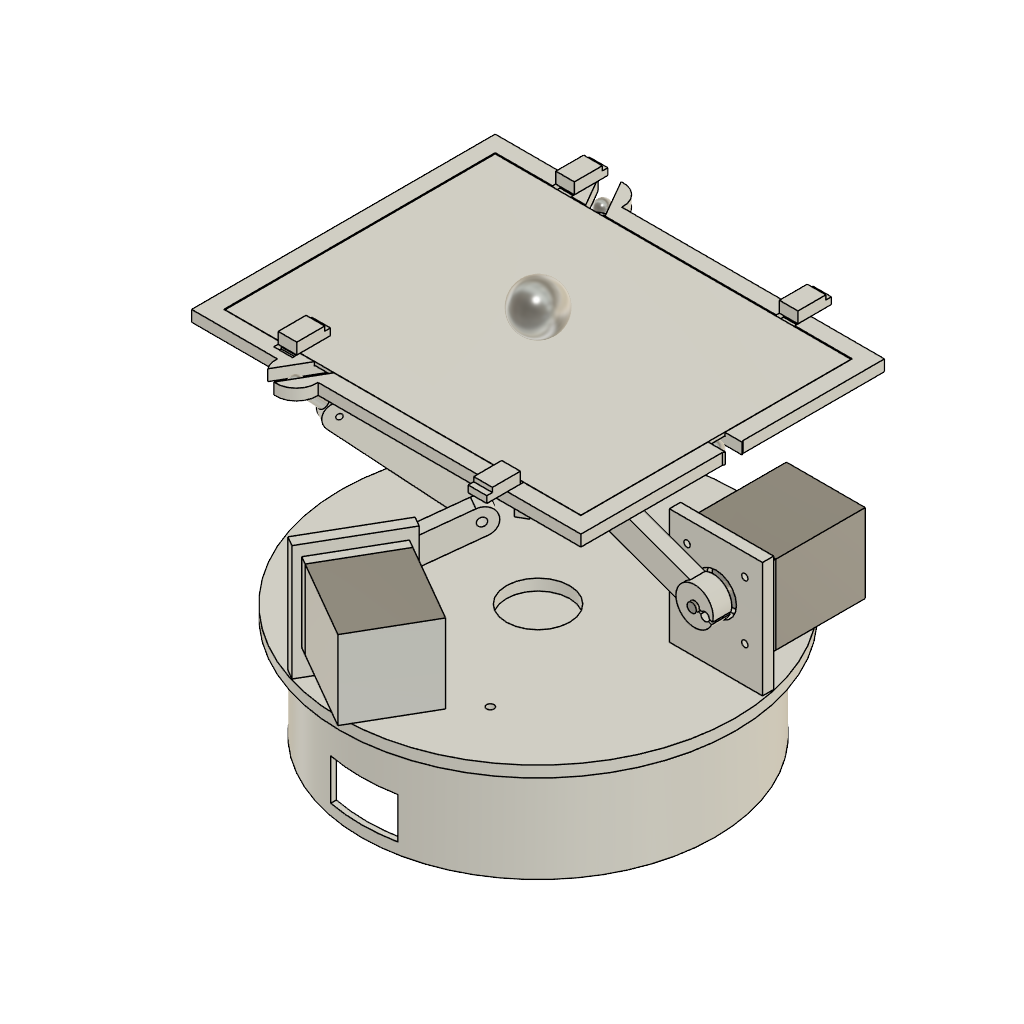
BallBalancer (Autodesk Fusion 360 design; units mm, degrees)
part number: 2026-11-05-17-29-33-825
part number: 2026-11-05-17-29-34-992
part number: 2026-11-05-17-29-35-798
part number: 2026-11-05-17-29-36-320
part number: 2026-11-05-17-29-37-063
description: 22 mm M3 tie rod with ball ends, bought in
part number: 2026-11-05-17-29-37-542
description: Reference geometry, not a printed part
part number: 2026-11-05-17-29-37-865
part number: 2026-11-05-17-29-38-263
part number: 2026-11-05-17-29-38-994
description: 8.4 inch 4 wire resistive panel, reference geometry
part number: 2026-11-05-17-29-40-592
description: 1 inch steel bearing ball, reference geometry
part number: 2026-11-05-17-29-40-774
part number: 2026-11-05-17-29-40-973
Autodesk Fusion 360 part; units mm, degrees
note: some values were not read from the file. Set by a fixed rule: which sketch regions a step uses.
sketch "plate_outline" plane through (0, 0, 0) normal (0, 0, 1) x (1, 0, 0) in component "base_plate"
  circle A0 centre (0, 0) radius 106
extrude "Extrude1" add sketch "plate_outline" against normal blind 6 makes body 1 in component "base_plate"
sketch "flange_0_footprint" plane through (0, 0, 0) normal (0, 0, 1) x (1, 0, 0) in component "base_plate"
  line L0 (53, 23.5) -> (103, 23.5)
  line L1 (103, 23.5) -> (103, 17.5)
  line L2 (103, 17.5) -> (53, 17.5)
  line L3 (53, 17.5) -> (53, 23.5)
extrude "Extrude2" add sketch "flange_0_footprint" along normal blind 62 bodies 1 in component "base_plate"
sketch "flange_1_footprint" plane through (0, 0, 0) normal (0, 0, 1) x (1, 0, 0) in component "base_plate"
  line L0 (-46.8516, 34.1493) -> (-71.8516, 77.4506)
  line L1 (-71.8516, 77.4506) -> (-66.6554, 80.4506)
  line L2 (-66.6554, 80.4506) -> (-41.6554, 37.1493)
  line L3 (-41.6554, 37.1493) -> (-46.8516, 34.1493)
extrude "Extrude3" add sketch "flange_1_footprint" along normal blind 62 bodies 1 in component "base_plate"
sketch "flange_2_footprint" plane through (0, 0, 0) normal (0, 0, 1) x (1, 0, 0) in component "base_plate"
  line L0 (-6.1484, -57.6493) -> (-31.1484, -100.9506)
  line L1 (-31.1484, -100.9506) -> (-36.3446, -97.9506)
  line L2 (-36.3446, -97.9506) -> (-11.3446, -54.6493)
  line L3 (-11.3446, -54.6493) -> (-6.1484, -57.6493)
extrude "Extrude4" add sketch "flange_2_footprint" along normal blind 62 bodies 1 in component "base_plate"
sketch "leg_0_plane_axis" plane through (0, 0, 0) normal (0, 0, 1) x (1, 0, 0) in component "base_plate"
  line L0 (0, 0) -> (150, 0)
ref_plane "WorkPlane1" through (75, 0, 0) normal (0, -1, 0) x (1, 0, 0) in component "base_plate"
sketch "flange_0_holes" plane through (0, 0, 0) normal (0, -1, 0) x (-1, 0, 0) in component "base_plate"
  circle A0 centre (-62.5, -19.5) radius 1.7
  circle A1 centre (-62.5, -50.5) radius 1.7
  circle A2 centre (-93.5, -19.5) radius 1.7
  circle A3 centre (-93.5, -50.5) radius 1.7
  circle A4 centre (-78, -35) radius 11
extrude "Extrude5" cut sketch "flange_0_holes" along normal mid plane 160 bodies 1 in component "base_plate"
sketch "leg_1_plane_axis" plane through (0, 0, 0) normal (0, 0, 1) x (1, 0, 0) in component "base_plate"
  line L0 (0, 0) -> (-75, 129.9038)
ref_plane "WorkPlane2" through (-37.5, 64.9519, 0) normal (0.866025, 0.5, 0) x (-0.5, 0.866025, 0) in component "base_plate"
sketch "flange_1_holes" plane through (0, 0, 0) normal (0.866025, 0.5, 0) x (-0.5, 0.866025, 0) in component "base_plate"
  circle A0 centre (62.5, 19.5) radius 1.7
  circle A1 centre (62.5, 50.5) radius 1.7
  circle A2 centre (93.5, 19.5) radius 1.7
  circle A3 centre (93.5, 50.5) radius 1.7
  circle A4 centre (78, 35) radius 11
extrude "Extrude6" cut sketch "flange_1_holes" along normal mid plane 160 bodies 1 in component "base_plate"
sketch "leg_2_plane_axis" plane through (0, 0, 0) normal (0, 0, 1) x (1, 0, 0) in component "base_plate"
  line L0 (0, 0) -> (-75, -129.9038)
ref_plane "WorkPlane3" through (-37.5, -64.9519, 0) normal (-0.866025, 0.5, 0) x (-0.5, -0.866025, 0) in component "base_plate"
sketch "flange_2_holes" plane through (0, 0, 0) normal (-0.866025, 0.5, 0) x (-0.5, -0.866025, 0) in component "base_plate"
  circle A0 centre (62.5, 19.5) radius 1.7
  circle A1 centre (62.5, 50.5) radius 1.7
  circle A2 centre (93.5, 19.5) radius 1.7
  circle A3 centre (93.5, 50.5) radius 1.7
  circle A4 centre (78, 35) radius 11
extrude "Extrude7" cut sketch "flange_2_holes" along normal mid plane 160 bodies 1 in component "base_plate"
sketch "insert_holes" plane through (0, 0, 0) normal (0, 0, 1) x (1, 0, 0) in component "base_plate"
  circle A0 centre (35, 60.6218) radius 2
  circle A1 centre (-70, 0) radius 2
  circle A2 centre (35, -60.6218) radius 2
extrude "Extrude8" cut sketch "insert_holes" against normal blind 6 bodies 1 in component "base_plate"
sketch "cable_hole" plane through (0, 0, 0) normal (0, 0, 1) x (1, 0, 0) in component "base_plate"
  circle A0 centre (0, 0) radius 17
extrude "Extrude9" cut sketch "cable_hole" along normal mid plane 160 bodies 1 in component "base_plate"
sketch "stand_outline" plane through (0, 0, 0) normal (0, 0, 1) x (1, 0, 0) in component "base_stand"
  circle A0 centre (0, 0) radius 95
extrude "Extrude1'" add sketch "stand_outline" against normal blind 55 from surface at -6 separate body makes body 2 in component "base_stand"
sketch "stand_cavity" plane through (0, 0, 0) normal (0, 0, 1) x (1, 0, 0) in component "base_stand"
  circle A0 centre (0, 0) radius 92
extrude "Extrude2'" cut sketch "stand_cavity" against normal blind 51 from surface at -10 bodies 2 in component "base_stand"
sketch "stand_bolt_holes" plane through (0, 0, 0) normal (0, 0, 1) x (1, 0, 0) in component "base_stand"
  circle A0 centre (35, 60.6218) radius 1.7
  circle A1 centre (-70, 0) radius 1.7
  circle A2 centre (35, -60.6218) radius 1.7
extrude "Extrude3'" cut sketch "stand_bolt_holes" along normal mid plane 160 bodies 2 in component "base_stand"
sketch "protoboard_inserts" plane through (0, 0, 0) normal (0, 0, 1) x (1, 0, 0) in component "base_stand"
  circle A0 centre (-30, -30) radius 2
  circle A1 centre (30, -30) radius 2
  circle A2 centre (30, 30) radius 2
  circle A3 centre (-30, 30) radius 2
extrude "Extrude4'" cut sketch "protoboard_inserts" against normal blind 6 from surface at -4 bodies 2 in component "base_stand"
sketch "cable_slot" plane through (0, 0, 0) normal (0, 0, 1) x (1, 0, 0) in component "base_stand"
  line L0 (-18, -100) -> (18, -100)
  line L1 (18, -100) -> (18, -87)
  line L2 (18, -87) -> (-18, -87)
  line L3 (-18, -87) -> (-18, -100)
extrude "Extrude5'" cut sketch "cable_slot" along normal blind 22 from surface at -55 bodies 2 in component "base_stand"
sketch "crank_profile" plane through (0, 0, 0) normal (0, 0, 1) x (1, 0, 0) in component "link_1_crank"
  circle A0 centre (0, 0) radius 10
  circle A1 centre (-55, 0) radius 7
  line L0 (0, -7) -> (-55, -7)
  line L1 (0, 7) -> (-55, 7)
  line L2 (0, -7) -> (0, 7)
  line L3 (-55, -7) -> (-55, 7)
extrude "Extrude1''" add sketch "crank_profile" along normal blind 8 separate body makes body 3 in component "link_1_crank"
sketch "hub" plane through (0, 0, 0) normal (0, 0, 1) x (1, 0, 0) in component "link_1_crank"
  circle A0 centre (0, 0) radius 10
extrude "Extrude2''" add sketch "hub" along normal blind 10 bodies 3 in component "link_1_crank"
sketch "shaft_bore" plane through (0, 0, 0) normal (0, 0, 1) x (1, 0, 0) in component "link_1_crank"
  circle A0 centre (0, 0) radius 2.575
extrude "Extrude3''" cut sketch "shaft_bore" along normal mid plane 160 bodies 3 in component "link_1_crank"
sketch "clamp_slot" plane through (0, 0, 0) normal (0, 0, 1) x (1, 0, 0) in component "link_1_crank"
  line L0 (1, -0.7) -> (11, -0.7)
  line L1 (11, -0.7) -> (11, 0.7)
  line L2 (11, 0.7) -> (1, 0.7)
  line L3 (1, 0.7) -> (1, -0.7)
extrude "Extrude4''" cut sketch "clamp_slot" along normal mid plane 160 bodies 3 in component "link_1_crank"
sketch "clamp_screw" plane through (0, 0, 0) normal (0, 0, 1) x (1, 0, 0) in component "link_1_crank"
  circle A0 centre (6, 0) radius 2.25
extrude "Extrude5''" cut sketch "clamp_screw" along normal blind 12 from surface at -1 bodies 3 in component "link_1_crank"
sketch "knee_bore" plane through (0, 0, 0) normal (0, 0, 1) x (1, 0, 0) in component "link_1_crank"
  circle A0 centre (-55, 0) radius 2.25
extrude "Extrude6'" cut sketch "knee_bore" along normal mid plane 160 bodies 3 in component "link_1_crank"
sketch "coupler_profile" plane through (0, 0, 0) normal (0, 0, 1) x (1, 0, 0) in component "link_2_coupler"
  circle A0 centre (0, 0) radius 7
  circle A1 centre (73, 0) radius 7
  line L0 (0, -7) -> (73, -7)
  line L1 (0, 7) -> (73, 7)
  line L2 (0, -7) -> (0, 7)
  line L3 (73, -7) -> (73, 7)
extrude "Extrude1'''" add sketch "coupler_profile" along normal blind 8 separate body makes body 4 in component "link_2_coupler"
sketch "coupler_bores" plane through (0, 0, 0) normal (0, 0, 1) x (1, 0, 0) in component "link_2_coupler"
  circle A0 centre (0, 0) radius 2.25
  circle A1 centre (73, 0) radius 1.45
extrude "Extrude2'''" cut sketch "coupler_bores" along normal mid plane 160 bodies 4 in component "link_2_coupler"
sketch "rod_axis" plane through (0, 0, 0) normal (0, 0, 1) x (1, 0, 0) in component "tie_rod"
  line L0 (0, 0) -> (22, 0)
  line L1 (7, 0) -> (7, 3)
  line L2 (7, 3) -> (22, 3)
  line L3 (22, 3) -> (22, 0)
revolve "Revolve1" add sketch "rod_axis" angle 360 about axis through (0, 0, 0) along (1, 0, 0) separate body makes body 5 in component "tie_rod"
sketch "ball_end" plane through (0, 0, 0) normal (0, 0, 1) x (1, 0, 0) in component "tie_rod"
  line L0 (18, 0) -> (26, 0)
  arc A0 (26, 0) -> (18, 0) centre (22, 0) ccw
revolve "Revolve2" add sketch "ball_end" angle 360 about axis through (18, 0, 0) along (1, 0, 0) bodies 5 in component "tie_rod"
sketch "motor_body" plane through (0, 0, 0) normal (0, 0, 1) x (1, 0, 0) in component "nema17_reference"
  line L0 (-21.15, -21.15) -> (21.15, -21.15)
  line L1 (21.15, -21.15) -> (21.15, 21.15)
  line L2 (21.15, 21.15) -> (-21.15, 21.15)
  line L3 (-21.15, 21.15) -> (-21.15, -21.15)
extrude "Extrude1''''" add sketch "motor_body" against normal blind 48 separate body makes body 6 in component "nema17_reference"
sketch "pilot_boss" plane through (0, 0, 0) normal (0, 0, 1) x (1, 0, 0) in component "nema17_reference"
  circle A0 centre (0, 0) radius 11
extrude "Extrude2''''" add sketch "pilot_boss" along normal blind 2 bodies 6 in component "nema17_reference"
sketch "shaft" plane through (0, 0, 0) normal (0, 0, 1) x (1, 0, 0) in component "nema17_reference"
  circle A0 centre (0, 0) radius 2.5
extrude "Extrude3'''" add sketch "shaft" along normal blind 24 bodies 6 in component "nema17_reference"
sketch "spacer_outline" plane through (0, 0, 0) normal (0, 0, 1) x (1, 0, 0) in component "motor_spacer"
  line L0 (-21.15, -21.15) -> (21.15, -21.15)
  line L1 (21.15, -21.15) -> (21.15, 21.15)
  line L2 (21.15, 21.15) -> (-21.15, 21.15)
  line L3 (-21.15, 21.15) -> (-21.15, -21.15)
extrude "Extrude1'''''" add sketch "spacer_outline" along normal blind 5 separate body makes body 7 in component "motor_spacer"
sketch "spacer_holes" plane through (0, 0, 0) normal (0, 0, 1) x (1, 0, 0) in component "motor_spacer"
  circle A0 centre (-15.5, -15.5) radius 1.7
  circle A1 centre (-15.5, 15.5) radius 1.7
  circle A2 centre (15.5, -15.5) radius 1.7
  circle A3 centre (15.5, 15.5) radius 1.7
  circle A4 centre (0, 0) radius 11.5
extrude "Extrude2'''''" cut sketch "spacer_holes" along normal mid plane 160 bodies 7 in component "motor_spacer"
sketch "frame_outline" plane through (0, 0, 0) normal (0, 0, 1) x (1, 0, 0) in component "platform_frame"
  line L0 (-104.5, -81.5) -> (104.5, -81.5)
  line L1 (104.5, -81.5) -> (104.5, 81.5)
  line L2 (104.5, 81.5) -> (-104.5, 81.5)
  line L3 (-104.5, 81.5) -> (-104.5, -81.5)
  circle A0 centre (95, 0) radius 11
  circle A1 centre (-47.5, 82.2724) radius 11
  circle A2 centre (-47.5, -82.2724) radius 11
extrude "Extrude1''''''" add sketch "frame_outline" along normal blind 6 separate body makes body 8 in component "platform_frame"
sketch "panel_recess" plane through (0, 0, 0) normal (0, 0, 1) x (1, 0, 0) in component "platform_frame"
  line L0 (-95.8, -72.8) -> (95.8, -72.8)
  line L1 (95.8, -72.8) -> (95.8, 72.8)
  line L2 (95.8, 72.8) -> (-95.8, 72.8)
  line L3 (-95.8, 72.8) -> (-95.8, -72.8)
extrude "Extrude2''''''" cut sketch "panel_recess" against normal blind 2 from surface at 6 bodies 8 in component "platform_frame"
sketch "frame_window" plane through (0, 0, 0) normal (0, 0, 1) x (1, 0, 0) in component "platform_frame"
  line L0 (-83.5, -60.5) -> (83.5, -60.5)
  line L1 (83.5, -60.5) -> (83.5, 60.5)
  line L2 (83.5, 60.5) -> (-83.5, 60.5)
  line L3 (-83.5, 60.5) -> (-83.5, -60.5)
extrude "Extrude3''''" cut sketch "frame_window" along normal mid plane 160 bodies 8 in component "platform_frame"
sketch "ear_clevis_slots" plane through (0, 0, 0) normal (0, 0, 1) x (1, 0, 0) in component "platform_frame"
  line L0 (82, 4.5) -> (108, 4.5)
  line L1 (108, 4.5) -> (108, -4.5)
  line L2 (108, -4.5) -> (82, -4.5)
  line L3 (82, -4.5) -> (82, 4.5)
  line L4 (-44.8971, 68.7641) -> (-57.8971, 91.2807)
  line L5 (-57.8971, 91.2807) -> (-50.1029, 95.7807)
  line L6 (-50.1029, 95.7807) -> (-37.1029, 73.2641)
  line L7 (-37.1029, 73.2641) -> (-44.8971, 68.7641)
  line L8 (-37.1029, -73.2641) -> (-50.1029, -95.7807)
  line L9 (-50.1029, -95.7807) -> (-57.8971, -91.2807)
  line L10 (-57.8971, -91.2807) -> (-44.8971, -68.7641)
  line L11 (-44.8971, -68.7641) -> (-37.1029, -73.2641)
extrude "Extrude4'''" cut sketch "ear_clevis_slots" along normal mid plane 160 bodies 8 in component "platform_frame"
sketch "ear_bores" plane through (0, 0, 0) normal (0, 0, 1) x (1, 0, 0) in component "platform_frame"
  circle A0 centre (95, 0) radius 1.7
  circle A1 centre (-47.5, 82.2724) radius 1.7
  circle A2 centre (-47.5, -82.2724) radius 1.7
extrude "Extrude5'''" cut sketch "ear_bores" along normal mid plane 160 bodies 8 in component "platform_frame"
sketch "clip_slots" plane through (0, 0, 0) normal (0, 0, 1) x (1, 0, 0) in component "platform_frame"
  line L0 (-65, -76.8) -> (-55, -76.8)
  line L1 (-55, -76.8) -> (-55, -72.8)
  line L2 (-55, -72.8) -> (-65, -72.8)
  line L3 (-65, -72.8) -> (-65, -76.8)
  line L4 (-65, 72.8) -> (-55, 72.8)
  line L5 (-55, 72.8) -> (-55, 76.8)
  line L6 (-55, 76.8) -> (-65, 76.8)
  line L7 (-65, 76.8) -> (-65, 72.8)
  line L8 (55, -76.8) -> (65, -76.8)
  line L9 (65, -76.8) -> (65, -72.8)
  line L10 (65, -72.8) -> (55, -72.8)
  line L11 (55, -72.8) -> (55, -76.8)
  line L12 (55, 72.8) -> (65, 72.8)
  line L13 (65, 72.8) -> (65, 76.8)
  line L14 (65, 76.8) -> (55, 76.8)
  line L15 (55, 76.8) -> (55, 72.8)
extrude "Extrude6''" cut sketch "clip_slots" against normal blind 3 from surface at 6 bodies 8 in component "platform_frame"
sketch "panel_outline" plane through (0, 0, 0) normal (0, 0, 1) x (1, 0, 0) in component "touch_panel_8p4"
  line L0 (-95.5, -72.5) -> (95.5, -72.5)
  line L1 (95.5, -72.5) -> (95.5, 72.5)
  line L2 (95.5, 72.5) -> (-95.5, 72.5)
  line L3 (-95.5, 72.5) -> (-95.5, -72.5)
extrude "Extrude1'''''''" add sketch "panel_outline" along normal blind 1.8 separate body makes body 9 in component "touch_panel_8p4"
sketch "ball_profile" plane through (0, 0, 0) normal (0, 0, 1) x (1, 0, 0) in component "ball_1in"
  line L0 (0, -12.7) -> (0, 12.7)
  arc A0 (0, -12.7) -> (0, 12.7) centre (0, 0) ccw
revolve "Revolve1'" add sketch "ball_profile" angle 360 about axis through (0, -12.7, 0) along (0, 1, 0) separate body makes body 10 in component "ball_1in"
sketch "clip_profile" plane through (0, 0, 0) normal (0, 0, 1) x (1, 0, 0) in component "retainer_clip"
  line L0 (-5, 0) -> (5, 0)
  line L1 (5, 0) -> (5, 18)
  line L2 (5, 18) -> (-5, 18)
  line L3 (-5, 18) -> (-5, 0)
extrude "Extrude1''''''''" add sketch "clip_profile" along normal blind 6 separate body makes body 11 in component "retainer_clip"
sketch "clip_lip" plane through (0, 0, 0) normal (0, 0, 1) x (1, 0, 0) in component "retainer_clip"
  line L0 (-5, 15) -> (5, 15)
  line L1 (5, 15) -> (5, 18)
  line L2 (5, 18) -> (-5, 18)
  line L3 (-5, 18) -> (-5, 15)
extrude "Extrude2'''''''" cut sketch "clip_lip" against normal blind 2.4 from surface at 6 bodies 11 in component "retainer_clip"
component "base_plate" placed x (1, 0, 0) y (0, 1, 0) z (0, 0, 1) at (0, 0, 0)
component "base_stand" placed x (1, 0, 0) y (0, 1, 0) z (0, 0, 1) at (0, 0, 0)
component "link_1_crank" placed x (0.939693, 0, -0.34202) y (0.34202, 0, 0.939693) z (0, -1, 0) at (78, 16, 35)
component "link_2_coupler" placed x (0.72298, 0, 0.690869) y (-0.690869, 0, 0.72298) z (0, -1, 0) at (26.3169, 4, 53.8111)
component "tie_rod" placed x (0.72298, 0, 0.690869) y (-0.690869, 0, 0.72298) z (0, -1, 0) at (79.0944, 0, 104.2445)
component "nema17_reference" placed x (1, 0, 0) y (0, 0, 1) z (0, -1, 0) at (78, 28.5, 35)
component "motor_spacer" placed x (1, 0, 0) y (0, 0, 1) z (0, -1, 0) at (78, 28.5, 35)
component "link_1_crank" placed x (-0.469846, 0.813798, -0.34202) y (-0.17101, 0.296198, 0.939693) z (0.866025, 0.5, 0) at (-52.8564, 59.55, 35)
component "link_2_coupler" placed x (-0.36149, 0.626119, 0.690869) y (0.345435, -0.59831, 0.72298) z (0.866025, 0.5, 0) at (-16.6226, 20.7911, 53.8111)
component "tie_rod" placed x (-0.36149, 0.626119, 0.690869) y (0.345435, -0.59831, 0.72298) z (0.866025, 0.5, 0) at (-39.5472, 68.4978, 104.2445)
component "nema17_reference" placed x (-0.5, 0.866025, 0) y (0, 0, 1) z (0.866025, 0.5, 0) at (-63.6817, 53.3, 35)
component "motor_spacer" placed x (-0.5, 0.866025, 0) y (0, 0, 1) z (0.866025, 0.5, 0) at (-63.6817, 53.3, 35)
component "link_1_crank" placed x (-0.469846, -0.813798, -0.34202) y (-0.17101, -0.296198, 0.939693) z (-0.866025, 0.5, 0) at (-25.1436, -75.55, 35)
component "link_2_coupler" placed x (-0.36149, -0.626119, 0.690869) y (0.345435, 0.59831, 0.72298) z (-0.866025, 0.5, 0) at (-9.6944, -24.7911, 53.8111)
component "tie_rod" placed x (-0.36149, -0.626119, 0.690869) y (0.345435, 0.59831, 0.72298) z (-0.866025, 0.5, 0) at (-39.5472, -68.4978, 104.2445)
component "nema17_reference" placed x (-0.5, -0.866025, 0) y (0, 0, 1) z (-0.866025, 0.5, 0) at (-14.3183, -81.8, 35)
component "motor_spacer" placed x (-0.5, -0.866025, 0) y (0, 0, 1) z (-0.866025, 0.5, 0) at (-14.3183, -81.8, 35)
component "platform_frame" placed x (1, 0, 0) y (0, 1, 0) z (0, 0, 1) at (0, 0, 119.4437)
component "touch_panel_8p4" placed x (1, 0, 0) y (0, 1, 0) z (0, 0, 1) at (0, 0, 123.4437)
component "ball_1in" placed x (1, 0, 0) y (0, 1, 0) z (0, 0, 1) at (0, 0, 137.9437)
component "retainer_clip" placed x (1, 0, 0) y (0, 1, 0) z (0, 0, 1) at (-60, -74.5, 125.4437)
component "retainer_clip" placed x (1, 0, 0) y (0, 1, 0) z (0, 0, 1) at (-60, 74.5, 125.4437)
component "retainer_clip" placed x (-1, 0, 0) y (0, -1, 0) z (0, 0, 1) at (60, -74.5, 125.4437)
component "retainer_clip" placed x (1, 0, 0) y (0, 1, 0) z (0, 0, 1) at (60, 74.5, 125.4437)
component "(Unsaved)" placed x (1, 0, 0) y (0, 1, 0) z (0, 0, 1) at (0, 0, 0) in component "link_2_coupler"
equation "base_motor_r = 78.0 mm" comment "centre to crank pivot axis"
equation "platform_joint_r = 95.0 mm" comment "platform centre to tie rod ball centre"
equation "crank_len = 55.0 mm" comment "crank pivot to knee"
equation "link2_len = 73.0 mm" comment "knee to tie rod thread"
equation "tie_rod_len = 22.0 mm" comment "tie rod between ball centres"
equation "motor_shaft_z = 35.0 mm" comment "crank pivot height above base plate top"
equation "crank_home_angle = 20.0 deg" comment "crank angle with the platform level"
equation "crank_min_angle = -20.0 deg" comment "lower mechanical travel limit"
equation "crank_max_angle = 60.0 deg" comment "upper mechanical travel limit"
equation "panel_w = 191.0 mm" comment "8.4 inch resistive panel, long edge"
equation "panel_h = 145.0 mm" comment "8.4 inch resistive panel, short edge"
equation "panel_t = 1.8 mm" comment "panel thickness"
equation "frame_border = 9.0 mm"
equation "frame_t = 6.0 mm"
equation "panel_recess = 2.0 mm"
equation "ear_r = 11.0 mm"
equation "base_plate_r = 106.0 mm"
equation "base_plate_t = 6.0 mm"
equation "stand_r = 95.0 mm"
equation "stand_h = 55.0 mm"
equation "stand_wall = 3.0 mm"
equation "stand_deck_t = 4.0 mm"
equation "stand_bolt_r = 70.0 mm"
equation "nema_sq = 42.3 mm"
equation "nema_bolt = 31.0 mm" comment "NEMA 17 bolt circle, square pattern"
equation "nema_pilot = 22.0 mm" comment "NEMA 17 pilot boss diameter"
equation "nema_len = 48.0 mm"
equation "nema_shaft_d = 5.0 mm"
equation "nema_shaft_len = 24.0 mm"
equation "flange_t = 6.0 mm"
equation "flange_h = 62.0 mm"
equation "flange_w = 50.0 mm"
equation "spacer_t = 5.0 mm"
equation "crank_hub_d = 20.0 mm"
equation "crank_hub_w = 10.0 mm"
equation "crank_arm_w = 14.0 mm"
equation "crank_arm_t = 8.0 mm"
equation "knee_boss_d = 14.0 mm"
equation "coupler_w = 14.0 mm"
equation "coupler_t = 8.0 mm"
equation "tie_rod_d = 6.0 mm"
equation "tie_rod_ball_d = 8.0 mm"
equation "m3_clear = 3.4 mm" comment "M3 clearance hole"
equation "m4_clear = 4.5 mm" comment "M4 clearance hole"
equation "m3_insert_d = 4.0 mm" comment "pilot for M3 x 6 heat set insert"
equation "m3_insert_depth = 6.0 mm"
equation "ball_d = 25.4 mm"
equation "clip_l = 18.0 mm"
equation "clip_w = 10.0 mm"
equation "clip_t = 6.0 mm"
equation "coupler_len = link2_len + tie_rod_len" comment "knee to ball centre"
equation "frame_w = panel_w + 2 * frame_border" comment "platform outer, long edge"
equation "frame_h = panel_h + 2 * frame_border" comment "platform outer, short edge"
named bodies: "plate", "stand", "crank", "coupler", "tie_rod", "motor", "spacer", "frame", "panel", "ball", "clip"
